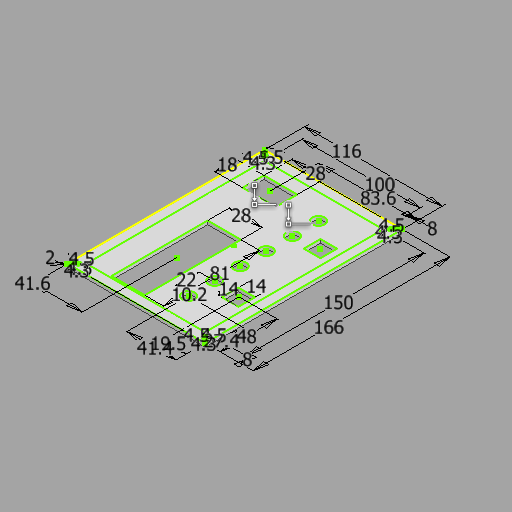
# Autodesk Inventor part: Part1
Saved by Autodesk Inventor 2027 (Build 310192000, 192)
## iProperties
Created: 2026-11-12
Part Number: Part1
Material: Generic
Document SubType Name: Modeling
Designer: jyjhm
Density: 1 g/cm^3
Appearance: Default
Author: jyjhm
Autodesk Inventor part; units mm, degrees
ref_plane "YZ Plane" through (0, 0, 0) normal (1, 0, 0) x (0, 1, 0)
ref_plane "XZ Plane" through (0, 0, 0) normal (0, 1, 0) x (-1, 0, 0)
ref_plane "XY Plane" through (0, 0, 0) normal (0, 0, 1) x (1, 0, 0)
sketch "Sketch1" plane through (0, 0, 0) normal (0, 1, 0) x (-1, 0, 0)
  line L0 (56, 82.5) -> (-56, 82.5)
  line L1 (-58, 80.5) -> (-58, -81.5)
  line L2 (-56, -83.5) -> (56, -83.5)
  line L3 (58, -81.5) -> (58, 80.5)
  line L4 (-45.5, 28) -> (-31.5, 28)
  line L5 (-31.5, 28) -> (-31.5, 42)
  line L6 (-31.5, 42) -> (-45.5, 42)
  line L7 (-45.5, 42) -> (-45.5, 28)
  line L8 (-30.6131, -28) -> (-44.6131, -28)
  line L9 (-44.6131, -28) -> (-44.6131, -42)
  line L10 (-44.6131, -42) -> (-30.6131, -42)
  line L11 (-30.6131, -42) -> (-30.6131, -28)
  circle A0 centre (-16.6, 55.1) radius 5.1
  circle A1 centre (-16.6, 33.1) radius 5.1
  circle A2 centre (-16.6, 11.6) radius 5.1
  circle A3 centre (-16.6, -10.4) radius 5.1
  circle A4 centre (-16.6, -32.4) radius 5.1
  circle A5 centre (-16.6, -54.4) radius 5.1
  line L12 (30.4, 73) -> (2.4, 73)
  line L13 (2.4, 73) -> (2.4, -8)
  line L14 (2.4, -8) -> (30.4, -8)
  line L15 (30.4, -8) -> (30.4, 73)
  line L16 (11.6, -64.7) -> (39.6, -64.7)
  line L17 (39.6, -64.7) -> (39.6, -46.7)
  line L18 (39.6, -46.7) -> (11.6, -46.7)
  line L19 (11.6, -46.7) -> (11.6, -64.7)
  line L20 (-50, -75.5) -> (50, -75.5)
  line L21 (50, -75.5) -> (50, 74.5)
  line L22 (50, 74.5) -> (-50, 74.5)
  line L23 (-50, 74.5) -> (-50, -75.5)
  arc A6 (58, 80.5) -> (56, 82.5) centre (56, 80.5) ccw
  arc A7 (56, -83.5) -> (58, -81.5) centre (56, -81.5) ccw
  arc A8 (-58, -81.5) -> (-56, -83.5) centre (-56, -81.5) ccw
  arc A9 (-56, 82.5) -> (-58, 80.5) centre (-56, 80.5) ccw
  circle A10 centre (53.5, -79) radius 2.15
  circle A11 centre (53.5, 78) radius 2.15
  circle A12 centre (-53.5, 78) radius 2.15
  circle A13 centre (-53.5, -79) radius 2.15
  point P0 (0, 0)
  point P1 (58, 82.5)
  point P2 (-58, -83.5)
  point P3 (-58, 82.5)
  point P4 (58, -83.5)
  point P5 (-38.5, 34.5)
  point P6 (-37.6131, -35)
  point P7 (16.4, 32)
  point P8 (25.6, -55.7)
  point P9 (0, 0)
  dimension "d0" = 166
  dimension "d1" = 116
  dimension "d2" = 19.5
  dimension "d3" = 48
  dimension "d7" = 10.2
  dimension "d8" = 14
  dimension "d11" = 14
  dimension "d15" = 27.4
  dimension "d22" = 41.4
  dimension "d23" = 22
  dimension "d36" = 83.6
  dimension "d37" = 28
  dimension "d38" = 18
  dimension "d39" = 81
  dimension "d40" = 28
  dimension "d41" = 41.6
  dimension "d43" = 100
  dimension "d50" = 150
  dimension "d68" = 8
  dimension "d71" = 8
  dimension "d72" = 2
  dimension "d79" = 4.3
  dimension "d80" = 4.5
  dimension "d81" = 4.5
  dimension "d82" = 4.3
  dimension "d83" = 4.3
  dimension "d84" = 4.3
  dimension "d85" = 4.5
  dimension "d86" = 4.5
  dimension "d87" = 4.5
  dimension "d88" = 4.5
  dimension "d89" = 4.5
  dimension "d90" = 4.5
  constraints: 48 end point, 14 centre point, 12 parallel, 8 point on circle, 8 point on line, 8 tangent, 6 horizontal, 6 perpendicular, 3 equal radius
  measures "d0" distance of point (58, -83.5) point (58, 82.5)
  measures "d1" distance of point (-58, -83.5) point (58, -83.5)
  measures "d2" distance from line of point (-38.5, 34.5) L1
  measures "d3" distance from line of L0 point (-38.5, 34.5)
  measures "d7" diameter of A0
  measures "d8" distance of L4.start L4.end
  measures "d11" distance of L4.end L5.end
  measures "d15" distance from line of L0 A0.centre
  measures "d22" distance from line of L1 A0.centre
  measures "d23" distance of A1.centre A0.centre
  measures "d36" distance from line of L1 point (25.6, -55.7)
  measures "d37" distance of L16.start L16.end
  measures "d38" distance of L16.end L17.end
  measures "d39" distance of L12.end L13.end
  measures "d40" distance of L13.end L14.end
  measures "d41" distance from line of L3 point (16.4, 32)
  measures "d43" distance of L20.start L20.end
  measures "d50" distance of L22.end L20.start
  measures "d68" distance between parallel lines of L22 L0
  measures "d71" distance between parallel lines of L1 L23
  measures "d72" radius of A6
  measures "d79" diameter of A10
  measures "d80" distance from line of L3 A10.centre
  measures "d81" distance from line of L2 A10.centre
  measures "d82" diameter of A11
  measures "d83" diameter of A12
  measures "d84" diameter of A13
  measures "d85" distance from line of L3 A11.centre
  measures "d86" distance from line of L0 A11.centre
  measures "d87" distance from line of L0 A12.centre
  measures "d88" distance from line of L1 A12.centre
  measures "d89" distance from line of A13.centre L1
  measures "d90" distance from line of L2 A13.centre
extrude "Extrusion1" add sketch "Sketch1" against normal blind 3 contours A6 L3 A7 L2 A8 L1 A9 L0 | L7 L6 L5 L4 | L11 L10 L9 L8 | A0 | A1 | A2 | A3 | A4 | A5 | L15 L14 L13 L12 | L19 L18 L17 L16 | L23 L22 L21 L20 | A10 | A11 | A12 | A13
extrude "Extrusion3" cut sketch "Sketch1" against normal blind 3 contours L7 L6 L5 L4 | L11 L10 L9 L8 | A0 | A1 | A2 | A3 | A4 | A5 | L15 L14 L13 L12 | L19 L18 L17 L16 | A10 | A11 | A12 | A13
sketch "Sketch6" plane through (0, 0, 0) normal (0, 1, 0) x (1, 0, 0)
  line L0 (-58, 81.5) -> (-58, -80.5) projected
  line L1 (56, 83.5) -> (-56, 83.5) projected
  point P0 (0, 0)
body "Solid1"
